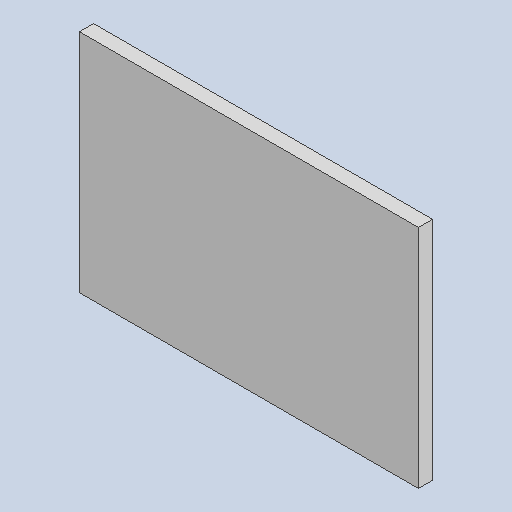
# Autodesk Inventor part: PRF-1003 Wall Entry
Saved by Autodesk Inventor 2026.2 (Build 302298000, 298)
## iProperties
Created: 2026-10-18
Part Number: PRF-1003 Wall Entry
Material: Generic
Description: Building wall, rough (sizes to confirm with customer)
Document SubType Name: Modeling
Designer: admin
Stock Number: Стена со входом (кирпич)
Density: 1 g/cm^3
Appearance: Default
Author: admin
Autodesk Inventor part; units mm, degrees
ref_plane "YZ Plane" through (0, 0, 0) normal (1, 0, 0) x (0, 1, 0)
ref_plane "XZ Plane" through (0, 0, 0) normal (0, 1, 0) x (-1, 0, 0)
ref_plane "XY Plane" through (0, 0, 0) normal (0, 0, 1) x (1, 0, 0)
sketch "Sketch1" plane through (0, 0, 0) normal (0, 1, 0) x (-1, 0, 0)
  line L0 (3000, 6000) -> (-3000, 6000)
  line L1 (-3000, 6000) -> (-3000, 6250)
  line L2 (-3000, 6250) -> (3000, 6250)
  line L3 (3000, 6250) -> (3000, 6000)
  constraints: 8 end point, 2 parallel, 1 horizontal, 1 perpendicular
extrude "Extrusion1" add sketch "Sketch1" along normal blind 4000
equation "\"d0\" = WallEntry1003_Height"
equation "\"WallEntry1003_Height\" = 4000"
body "Solid1"
